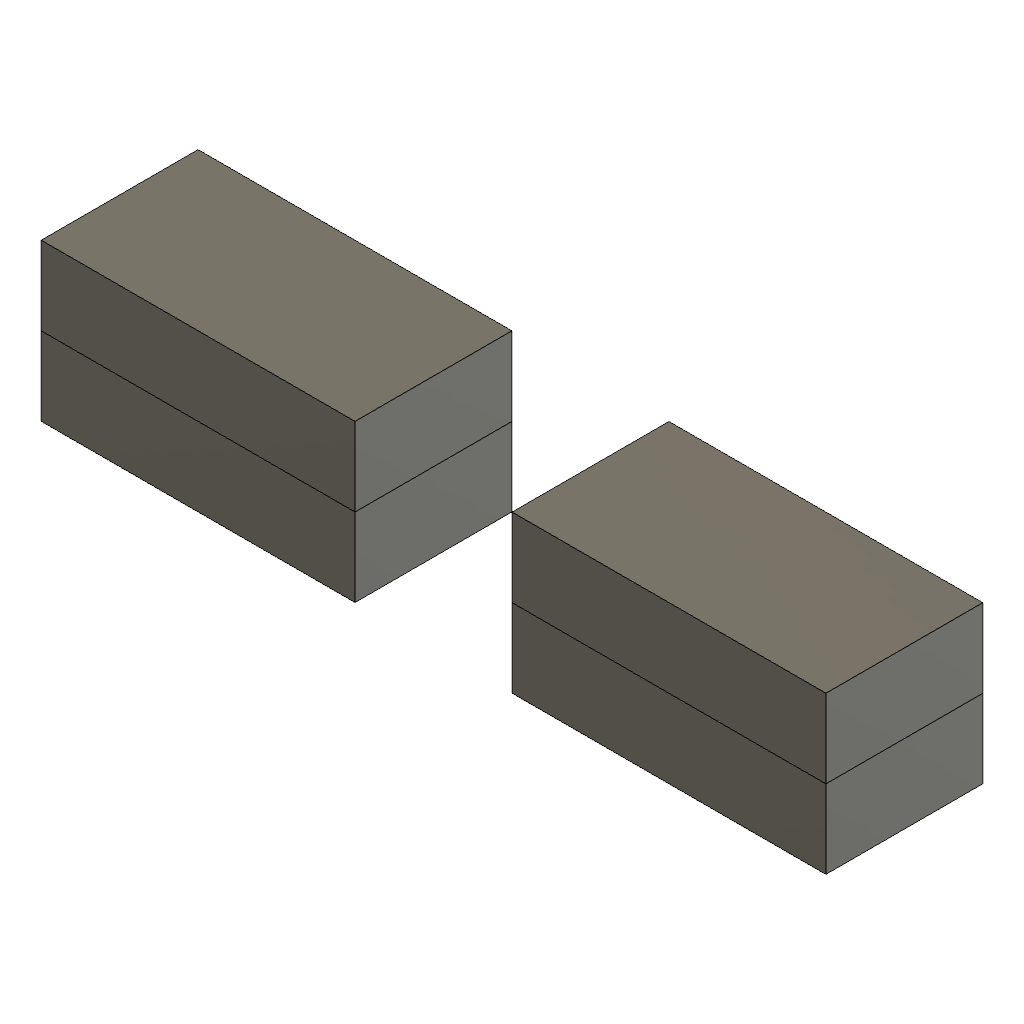
multiple_bodies (Autodesk Fusion 360 design; units mm, degrees)
part number: 2026-10-20-19-26-39-950
Autodesk Fusion 360 part; units mm, degrees
sketch "Sketch1" plane through (0, 0, 0) normal (0, 0, 1) x (1, 0, 0)
  line L0 (-20, -10) -> (20, -10)
  line L1 (20, -10) -> (20, 10)
  line L2 (20, 10) -> (-20, 10)
  line L3 (-20, 10) -> (-20, -10)
extrude "Extrude1" add sketch "Sketch1" along normal blind 20 makes body 1
sketch "Sketch2" plane through (0, 0, 0) normal (0, 0, 1) x (1, 0, 0)
  line L0 (40, -10) -> (80, -10)
  line L1 (80, -10) -> (80, 10)
  line L2 (80, 10) -> (40, 10)
  line L3 (40, 10) -> (40, -10)
extrude "Extrude2" add sketch "Sketch2" along normal blind 20 separate body makes body 2
split "ProbeSplit" by plane through (0, 0, 0) normal (0, 1, 0) bodies 1 2 makes body 4 at (66.6667, 10, 6.6667) makes body 3 at (6.6667, 10, 6.6667)
